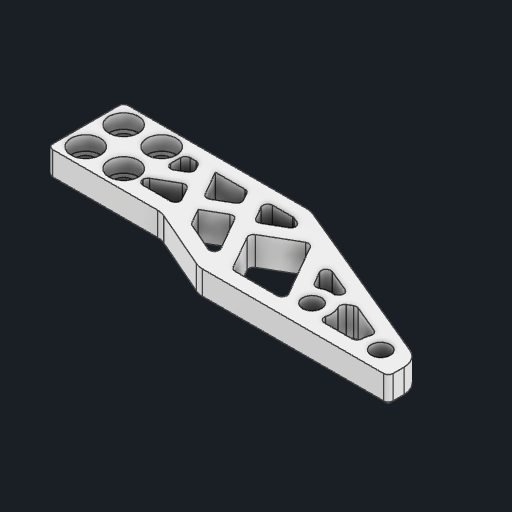
# Autodesk Inventor part: Tongs_R
Saved by Autodesk Inventor 2026.2 (Build 302298010, 298A)
## iProperties
Created: 2026-05-08
Part Number: Tongs_R
Material: ABS 플라스틱
Document SubType Name: Modeling
Designer: work
Density: 1.06 g/cm^3
Appearance: 매끄러움 - 흰색
Author: work
Autodesk Inventor part; units mm, degrees
ref_plane "YZ Plane" through (0, 0, 0) normal (1, 0, 0) x (0, 1, 0)
ref_plane "XZ Plane" through (0, 0, 0) normal (0, 1, 0) x (-1, 0, 0)
sketch "스케치1" plane through (0, 0, 0) normal (0, 1, 0) x (-1, 0, 0)
  line L0 (-4, 4) -> (4, 4) construction
  line L1 (4, 4) -> (4, -4) construction
  line L2 (4, -4) -> (-4, -4) construction
  line L3 (-4, -4) -> (-4, 4) construction
  line L4 (-4, 4) -> (4, -4) construction
  line L5 (4, 4) -> (-4, -4) construction
  circle A0 centre (4, 4) radius 2
  circle A1 centre (4, -4) radius 2
  circle A2 centre (-4, -4) radius 2
  circle A3 centre (-4, 4) radius 2
  line L6 (-8, 8) -> (8, 8)
  line L7 (8, 8) -> (8, -8)
  line L8 (8, -8) -> (-8, -8)
  line L9 (-8, -8) -> (-8, 8)
  line L10 (-8, 8) -> (8, -8) construction
  line L11 (8, 8) -> (-8, -8) construction
  line L12 (-8, 8) -> (-16, 8)
  line L13 (-16, 8) -> (-29.7477, 14)
  line L14 (-29.7477, 14) -> (-69.7477, 14)
  line L15 (-69.7477, 14) -> (-69.7477, 8)
  line L16 (-69.7477, 8) -> (-31.3982, -8)
  line L17 (-31.3982, -8) -> (-8, -8)
  line L18 (-8, -5) -> (-30.7974, -5)
  line L19 (-30.7974, -5) -> (-66.7477, 9.999)
  line L20 (-66.7477, 9.999) -> (-66.7477, 11)
  line L21 (-66.7477, 11) -> (-30.3739, 11)
  line L22 (-30.3739, 11) -> (-16.6261, 5)
  line L23 (-16.6261, 5) -> (-8, 5)
  line L24 (-48.5608, 11) -> (-42.0285, -0.3142)
  line L25 (-45.0967, 11) -> (-37.4652, -2.2181)
  line L26 (-30.3739, 11) -> (-21.1363, -5)
  line L27 (-33.838, 11) -> (-24.6004, -5)
  line L28 (-16.6261, 5) -> (-10.8526, -5)
  line L29 (-21.2571, 7.0211) -> (-14.3167, -5)
  line L30 (-37.4652, -2.2181) -> (-29.0212, 2.6571)
  line L31 (-27.5212, 0.059) -> (-33.9822, -3.6713)
  line L32 (-13.7394, 0) -> (-8, 3.3136)
  line L33 (-12.2394, -2.5981) -> (-8, -0.1505)
  line L34 (-17.7869, 1.0106) -> (-22.9016, -1.9424)
  line L35 (-24.4016, 0.6557) -> (-19.2869, 3.6086)
  line L36 (-46.0285, 6.614) -> (-51.3166, 3.5609)
  line L37 (-47.0285, 8.346) -> (-53.6386, 4.5297)
  point P0 (0, 0)
  point P1 (-30.7517, -1.8061)
  dimension "d0" = 8
  dimension "d1" = 8
  dimension "d2" = 4
  dimension "d3" = 4
  dimension "d4" = 4
  dimension "d5" = 4
  dimension "d6" = 4
  dimension "d7" = 8
  dimension "d8" = 15
  dimension "d9" = 40
  dimension "d10" = 6
  dimension "d11" = 38.3496
  dimension "d12" = 3
  dimension "d13" = 3
  dimension "d14" = 3
  dimension "d15" = 3
  dimension "d16" = 120
  dimension "d17" = 3
  dimension "d18" = 3
  dimension "d19" = 2
  dimension "d20" = 8
  dimension "d21" = 3
  constraints: 76 end point, 24 point on line, 19 parallel, 8 midpoint, 6 perpendicular, 4 centre point, 4 coincident, 3 horizontal, 5 other
  measures "d0" distance of L1.end L2.end
  measures "d1" distance of L0.end L1.end
  measures "d2" diameter of A0
  measures "d3" diameter of A1
  measures "d4" diameter of A2
  measures "d5" diameter of A3
  measures "d6" distance between parallel lines of L7 L1
  measures "d7" distance of L6.start L12.end
  measures "d8" distance of L12.end L13.end
  measures "d9" distance of L13.end L14.end
  measures "d10" distance of L14.end L15.end
  measures "d11" horizontal distance of L15.end L16.end
  measures "d12" distance between parallel lines of L13 L22
  measures "d13" distance between parallel lines of L24 L25
  measures "d14" distance between parallel lines of L27 L26
  measures "d15" distance between parallel lines of L29 L28
  measures "d16" angle of L21 L27
  measures "d17" distance between parallel lines of L34 L35
  measures "d18" distance from line of L30 point (-30.752, -1.806)
  measures "d19" distance between parallel lines of L37 L36
  measures "d20" distance from line of L24.end L36
  measures "d21" distance between parallel lines of L33 L32
extrude "돌출1" add sketch "스케치1" along normal blind 6 contours L6 L7 L8 L9 | L9 L23 L22 L21 L20 L19 L18 L17 L16 L15 L14 L13 L12 | L9 L33 L28 L32 | L28 L18 L29 L22 | L26 L18 L27 L21 | L29 L34 L26 L35 | L25 L19 L24 L21 | L27 L31 L19 L30 | L24 L36 L19 L37
sketch "스케치2" plane through (0, 6, 0) normal (0, 1, 0) x (1, 0, 0)
  line L0 (16, -8) -> (29.7477, -14) projected
  line L1 (29.7477, -14) -> (69.7477, -14) projected
  line L2 (69.7477, -14) -> (69.7477, -8) projected
  line L3 (69.7477, -8) -> (31.3982, 8) projected
  line L4 (31.3982, 8) -> (-8, 8) projected
  line L5 (-8, 8) -> (-8, -8) projected
  line L6 (-8, -8) -> (16, -8) projected
  line L7 (27.5212, -0.059) -> (24.6004, 5) projected
  line L8 (24.6004, 5) -> (30.7974, 5) projected
  line L9 (30.7974, 5) -> (33.9822, 3.6713) projected
  line L10 (33.9822, 3.6713) -> (27.5212, -0.059) projected
  line L11 (12.2394, 2.5981) -> (8, 0.1505) projected
  line L12 (8, 0.1505) -> (8, 5) projected
  line L13 (8, 5) -> (10.8526, 5) projected
  line L14 (10.8526, 5) -> (12.2394, 2.5981) projected
  line L15 (17.7869, -1.0106) -> (14.3167, 5) projected
  line L16 (14.3167, 5) -> (21.1363, 5) projected
  line L17 (21.1363, 5) -> (22.9016, 1.9424) projected
  line L18 (22.9016, 1.9424) -> (17.7869, -1.0106) projected
  line L19 (46.0285, -6.614) -> (42.0285, 0.3142) projected
  line L20 (42.0285, 0.3142) -> (51.3166, -3.5609) projected
  line L21 (51.3166, -3.5609) -> (46.0285, -6.614) projected
  line L22 (13.7394, 0) -> (16.6261, -5) projected
  line L23 (16.6261, -5) -> (8, -5) projected
  line L24 (8, -5) -> (8, -3.3136) projected
  line L25 (8, -3.3136) -> (13.7394, 0) projected
  line L26 (19.2869, -3.6086) -> (24.4016, -0.6557) projected
  line L27 (24.4016, -0.6557) -> (30.3739, -11) projected
  line L28 (30.3739, -11) -> (21.2571, -7.0211) projected
  line L29 (21.2571, -7.0211) -> (19.2869, -3.6086) projected
  line L30 (29.0212, -2.6571) -> (37.4652, 2.2181) projected
  line L31 (37.4652, 2.2181) -> (45.0967, -11) projected
  line L32 (45.0967, -11) -> (33.838, -11) projected
  line L33 (33.838, -11) -> (29.0212, -2.6571) projected
  circle A0 centre (4, -4) radius 2 projected
  circle A1 centre (4, 4) radius 2 projected
  circle A2 centre (-4, 4) radius 2 projected
  circle A3 centre (-4, -4) radius 2 projected
  line L34 (47.0285, -8.346) -> (53.6386, -4.5297) projected
  line L35 (53.6386, -4.5297) -> (66.7477, -9.999) projected
  line L36 (66.7477, -9.999) -> (66.7477, -11) projected
  line L37 (66.7477, -11) -> (48.5608, -11) projected
  line L38 (48.5608, -11) -> (47.0285, -8.346) projected
  point P0 (0, 0)
  constraints: 4 coincident
hole "구멍1" at (-4, 6, 4) at (4, 6, 4) at (4, 6, -4) at (-4, 6, -4) direction (0, -1, 0) diameter 4 end through all counterbore diameter 6.2 counterbore depth 3
fillet "모깎기1" radius 1 30 edges at (8, 3, -5) (8, 3, -0.1505) (10.8526, 3, -5) (12.2394, 3, -2.5981) (13.7394, 3, 0) (8, 3, 3.3136) (8, 3, 5) (16.6261, 3, 5) (17.7869, 3, 1.0106) (33.9822, 3, -3.6713) (30.7974, 3, -5) (27.5212, 3, 0.059) (24.6004, 3, -5) (22.9016, 3, -1.9424) (21.1363, 3, -5) (42.0285, 3, -0.3142) (46.0285, 3, 6.614) (53.6386, 3, 4.5297) (66.7477, 3, 9.999) (51.3166, 3, 3.5609) (24.4016, 3, 0.6557) (30.3739, 3, 11) (21.2571, 3, 7.0211) (45.0967, 3, 11) (37.4652, 3, -2.2181) (33.838, 3, 11) (29.0212, 3, 2.6571) (48.5608, 3, 11) (66.7477, 3, 11) (47.0285, 3, 8.346)
fillet "모깎기2" radius 4 4 edges at (16, 3, 8) (29.7477, 3, 14) (69.7477, 3, 8) (31.3982, 3, -8)
fillet "모깎기3" radius 1 3 edges at (-8, 3, 8) (-8, 3, -8) (69.7477, 3, 14)
chamfer "모따기1" distance 1 angle 45 14 edges at (29.7653, 0, 13.9156) (49.6652, 0, 14) (69.4548, 0, 13.7071) (69.7477, 0, 11.8327) (69.0764, 0, 8.4473) (49.7126, 0, -0.3589) (31.3826, 0, -7.9221) (11.7986, 0, -8) (-7.7071, 0, -7.7071) (-8, 0, 0) (-7.7071, 0, 7.7071) (4.0826, 0, 8) (15.9824, 0, 8.0844) (22.8739, 0, 11)
ref_plane "작업 평면1" through (0, 0, 0) normal (0, -1, 0) x (1, 0, 0)
sketch "스케치3" plane through (0, 6, 0) normal (0, 1, 0) x (1, 0, 0)
  circle A0 centre (-4, 4) radius 3.1 projected
  circle A1 centre (4, 4) radius 3.1 projected
  circle A2 centre (4, -4) radius 3.1 projected
  circle A3 centre (-4, -4) radius 3.1 projected
  arc A4 (68.7477, -14) -> (69.7477, -13) centre (68.7477, -13) ccw projected
  line L0 (69.7477, -13) -> (69.7477, -10.6653) projected
  arc A5 (69.7477, -10.6653) -> (67.2879, -6.9737) centre (65.7477, -10.6653) ccw projected
  line L1 (67.2879, -6.9737) -> (32.1374, 7.6916) projected
  arc A6 (32.1374, 7.6916) -> (30.5972, 8) centre (30.5972, 4) ccw projected
  line L2 (30.5972, 8) -> (-7, 8) projected
  arc A7 (-7, 8) -> (-8, 7) centre (-7, 7) ccw projected
  line L3 (-8, 7) -> (-8, -7) projected
  arc A8 (-8, -7) -> (-7, -8) centre (-7, -7) ccw projected
  line L4 (-7, -8) -> (15.1652, -8) projected
  arc A9 (16.7652, -8.3339) -> (15.1652, -8) centre (15.1652, -12) ccw projected
  line L5 (16.7652, -8.3339) -> (28.9826, -13.6661) projected
  arc A10 (28.9826, -13.6661) -> (30.5826, -14) centre (30.5826, -10) ccw projected
  line L6 (30.5826, -14) -> (68.7477, -14) projected
  line L7 (27.0212, 0.807) -> (25.4664, 3.5) projected
  arc A11 (26.3324, 5) -> (25.4664, 3.5) centre (26.3324, 4) ccw projected
  line L8 (26.3324, 5) -> (30.5972, 5) projected
  arc A12 (30.9822, 4.9229) -> (30.5972, 5) centre (30.5972, 4) ccw projected
  line L9 (30.9822, 4.9229) -> (32.1168, 4.4496) projected
  arc A13 (32.2317, 2.6606) -> (32.1168, 4.4496) centre (31.7317, 3.5267) ccw projected
  line L10 (32.2317, 2.6606) -> (28.3872, 0.441) projected
  arc A14 (27.0212, 0.807) -> (28.3872, 0.441) centre (27.8872, 1.307) ccw projected
  line L11 (11.3734, 2.0981) -> (9.5, 1.0165) projected
  arc A15 (8, 1.8825) -> (9.5, 1.0165) centre (9, 1.8825) ccw projected
  line L12 (8, 1.8825) -> (8, 4) projected
  arc A16 (9, 5) -> (8, 4) centre (9, 4) ccw projected
  line L13 (9, 5) -> (10.2753, 5) projected
  arc A17 (11.1413, 4.5) -> (10.2753, 5) centre (10.2753, 4) ccw projected
  line L14 (11.1413, 4.5) -> (11.7394, 3.4641) projected
  arc A18 (11.3734, 2.0981) -> (11.7394, 3.4641) centre (10.8734, 2.9641) ccw projected
  line L15 (17.2869, -0.1445) -> (14.3167, 5) projected
  line L16 (14.3167, 5) -> (20.5589, 5) projected
  arc A19 (21.4249, 4.5) -> (20.5589, 5) centre (20.5589, 4) ccw projected
  line L17 (21.4249, 4.5) -> (22.4016, 2.8084) projected
  arc A20 (22.0356, 1.4424) -> (22.4016, 2.8084) centre (21.5356, 2.3084) ccw projected
  line L18 (22.0356, 1.4424) -> (18.653, -0.5106) projected
  arc A21 (17.2869, -0.1445) -> (18.653, -0.5106) centre (18.153, 0.3555) ccw projected
  line L19 (45.5285, -5.748) -> (43.5077, -2.2478) projected
  arc A22 (44.7588, -0.8249) -> (43.5077, -2.2478) centre (44.3737, -1.7478) ccw projected
  line L20 (44.7588, -0.8249) -> (49.4512, -2.7826) projected
  arc A23 (49.5661, -4.5715) -> (49.4512, -2.7826) centre (49.0661, -3.7055) ccw projected
  line L21 (49.5661, -4.5715) -> (46.8946, -6.114) projected
  arc A24 (45.5285, -5.748) -> (46.8946, -6.114) centre (46.3946, -5.248) ccw projected
  line L22 (14.2394, -0.866) -> (15.7601, -3.5) projected
  arc A25 (14.8941, -5) -> (15.7601, -3.5) centre (14.8941, -4) ccw projected
  line L23 (14.8941, -5) -> (9, -5) projected
  arc A26 (8, -4) -> (9, -5) centre (9, -4) ccw projected
  line L24 (8, -4) -> (8, -3.891) projected
  arc A27 (8.5, -3.025) -> (8, -3.891) centre (9, -3.891) ccw projected
  line L25 (8.5, -3.025) -> (12.8734, -0.5) projected
  arc A28 (14.2394, -0.866) -> (12.8734, -0.5) centre (13.3734, -1.366) ccw projected
  line L26 (19.2869, -3.6086) -> (23.5356, -1.1557) projected
  arc A29 (24.9016, -1.5217) -> (23.5356, -1.1557) centre (24.0356, -2.0217) ccw projected
  line L27 (24.9016, -1.5217) -> (28.8541, -8.3677) projected
  arc A30 (27.5881, -9.7842) -> (28.8541, -8.3677) centre (27.9881, -8.8677) ccw projected
  line L28 (27.5881, -9.7842) -> (21.5587, -7.1527) projected
  arc A31 (21.0926, -6.7362) -> (21.5587, -7.1527) centre (21.9587, -6.2362) ccw projected
  line L29 (21.0926, -6.7362) -> (19.2869, -3.6086) projected
  line L30 (29.8872, -2.1571) -> (36.5992, 1.7181) projected
  arc A32 (37.9652, 1.3521) -> (36.5992, 1.7181) centre (37.0992, 0.8521) ccw projected
  line L31 (37.9652, 1.3521) -> (44.2307, -9.5) projected
  arc A33 (43.3646, -11) -> (44.2307, -9.5) centre (43.3646, -10) ccw projected
  line L32 (43.3646, -11) -> (34.4153, -11) projected
  arc A34 (33.5493, -10.5) -> (34.4153, -11) centre (34.4153, -10) ccw projected
  line L33 (33.5493, -10.5) -> (29.5212, -3.5231) projected
  arc A35 (29.8872, -2.1571) -> (29.5212, -3.5231) centre (30.3872, -3.0231) ccw projected
  line L34 (47.8946, -7.846) -> (53.2102, -4.7771) projected
  arc A36 (54.0952, -4.7202) -> (53.2102, -4.7771) centre (53.7102, -5.6431) ccw projected
  line L35 (54.0952, -4.7202) -> (64.5381, -9.0771) projected
  arc A37 (64.1531, -11) -> (64.5381, -9.0771) centre (64.1531, -10) ccw projected
  line L36 (64.1531, -11) -> (49.1381, -11) projected
  arc A38 (48.2721, -10.5) -> (49.1381, -11) centre (49.1381, -10) ccw projected
  line L37 (48.2721, -10.5) -> (47.5285, -9.2121) projected
  arc A39 (47.8946, -7.846) -> (47.5285, -9.2121) centre (48.3946, -8.7121) ccw projected
  circle A40 centre (64.1531, -10) radius 4
  circle A41 centre (64.1531, -10) radius 2
  arc A42 (47.8946, -7.846) -> (47.5285, -9.2121) centre (48.3946, -8.7121) ccw projected
  circle A43 centre (48.3946, -8.7121) radius 4
  circle A44 centre (48.3946, -8.7121) radius 2
  point P0 (0, 0)
  point P1 (62.421, -11)
  point P2 (62.9396, -8.4102)
  point P3 (60.9637, -7.5858)
  point P4 (60.2801, -11)
  point P5 (49.3946, -6.98)
  point P6 (48.4356, -10.7116)
  point P7 (51.6756, -11)
  point P8 (51.2487, -5.9095)
  point P9 (49.1858, -4.7911)
  point P10 (45.5978, -5.8523)
  dimension "d38" = 8
  dimension "d41" = 4
  dimension "d42" = 8
  dimension "d43" = 4
  constraints: 4 centre point, 4 coincident
  measures "d38" diameter of A40
  measures "d41" diameter of A41
  measures "d42" diameter of A43
  measures "d43" diameter of A44
extrude "돌출2" add sketch "스케치3" against normal up to surface (6 mm away) contours A40 L35 A41 L36 | L36 A38 A44 L34 A43 | A43 L21 A24 picked at (60.9761, -9.0603)
extrude "돌출3" cut sketch "스케치3" along normal through all both and the other way through all contours L36 A37 L35 A41 | A44 L34 A39 L37 A38 picked at (63.6143, -8.5497) picked at (47.7626, -10.0688)
fillet "모깎기4" radius 1 5 edges at (60.2801, 3, 11) (60.9637, 3, 7.5858) (45.5978, 3, 5.8523) (51.2487, 3, 5.9095) (51.6756, 3, 11)
